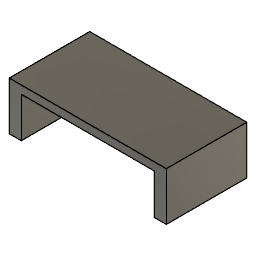
Battery Stand (Autodesk Fusion 360 design; units mm, degrees)
Autodesk Fusion 360 part; units mm, degrees
sketch "Sketch1" plane through (0, 0, 0) normal (0, 0, 1) x (1, 0, 0)
  line L0 (82.5, 45) -> (-82.5, 45)
  line L1 (-82.5, 45) -> (-82.5, -50)
  line L2 (-82.5, -45) -> (82.5, -45)
  line L3 (82.5, -50) -> (82.5, 45)
  line L4 (82.5, 45) -> (-82.5, -45) construction
  line L5 (-82.5, 45) -> (82.5, -45) construction
  line L6 (97.5, 50) -> (-97.5, 50)
  line L7 (-97.5, 50) -> (-97.5, -50)
  line L8 (-97.5, -50) -> (97.5, -50)
  line L9 (97.5, -50) -> (97.5, 50)
  line L10 (97.5, 50) -> (-97.5, -50) construction
  line L11 (-97.5, 50) -> (97.5, -50) construction
  dimension "d1" = 165
  dimension "d2" = 90
  dimension "d3" = 195
  dimension "d4" = 100
  constraint horizontal L0
  constraint perpendicular L0 L1
  constraint parallel L0 L2
  constraint parallel L1 L3
  constraint coincident L4 origin
  constraint coincident L5 origin
  constraint horizontal L6
  constraint perpendicular L6 L7
  constraint parallel L6 L8
  constraint parallel L7 L9
  constraint coincident L10 origin
  constraint coincident L11 origin
  constraint coincident L8 L1.end
  constraint coincident L2.start L1
  constraint coincident L8 L3.start
  constraint coincident L2.end L3
  measures "d1" distance of L2.start L2.end
  measures "d2" distance of L0.end L2.start
  measures "d3" distance of L7.end L8.end
  measures "d4" distance of L6.end L7.end
extrude "Extrude1" add sketch "Sketch1" along normal blind 50 contours L0 L1 L3 L6 L7 L8 L9
sketch "Sketch2" plane through (0, 0, 50) normal (0, 0, 1) x (-1, 0, 0)
  line L0 (-82.5, 50) -> (-97.5, 50)
  line L1 (-97.5, 50) -> (-97.5, -50)
  line L2 (-97.5, -50) -> (97.5, -50)
  line L3 (97.5, -50) -> (97.5, 50)
  line L4 (97.5, 50) -> (82.5, 50)
  line L5 (82.5, 50) -> (82.5, -45)
  line L6 (82.5, -45) -> (-82.5, -45)
  line L7 (-82.5, -45) -> (-82.5, 50)
  line L8 (97.5, -50) -> (-97.5, -50)
  line L9 (-97.5, -50) -> (-97.5, 50)
  line L10 (-97.5, 50) -> (97.5, 50)
  line L11 (97.5, 50) -> (97.5, -50)
  constraint horizontal L8
  constraint vertical L9
  constraint horizontal L10
  constraint vertical L11
  constraint coincident L0.end L1.start
  constraint coincident L2.end L3.start
extrude "Extrude2" add sketch "Sketch2" along normal blind 10
chamfer "Chamfer1" distance 50 angle 45 1 edges at (0, 45, 50) tangent chain off
